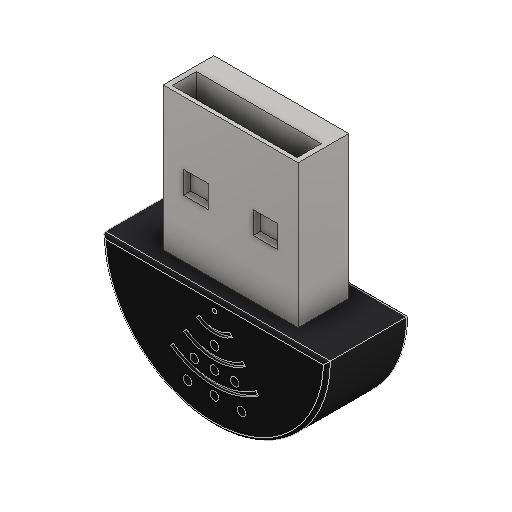
# Autodesk Inventor part: MI-305
Saved by Autodesk Inventor 2027 (Build 310192060, 192F)
## iProperties
Created: 2026-11-22
Part Number: MI-305
Material: 一般
Document SubType Name: Modeling
Designer: 王翊丞
Density: 1 g/cm^3
Appearance: 預設
Title: MI-305 USB 迷你麥克風
Author: 王翊丞
Comments: 照片重建的簡化外形。22 × 19 × 7 mm 為待量測參考尺寸。
Autodesk Inventor part; units mm, degrees
sketch "外殼半橢圓輪廓" plane through (0, 0, 0) normal (0, 0, 1) x (1, 0, 0)
  ellipse E0 centre (0, 0) end of major axis (10, 0) minor radius 9.9 (-10, 0) -> (10, 0) ccw
  line L0 (-10, 0) -> (10, 0)
  dimension "d0" = 10
  dimension "d1" = 9.9
  constraints: 2 end point, 2 horizontal alignment, 1 coincident, 5 other
extrude "外殼擠出" add sketch "外殼半橢圓輪廓" along normal blind 7.4
fillet "外殼上下緣圓角" radius 0.3 4 edges at (0, 0, 0) (0, 0, 7.4) (0, -9.9, 0) (0, -9.9, 7.4)
ref_plane "USB 底面基準" through (0, 0, 1.45) normal (0, 0, 1) x (1, 0, 0)
sketch "USB-A 外廓" plane through (0, 0, 1.45) normal (0, 0, 1) x (1, 0, 0)
  line L0 (-6, 0) -> (6, 0)
  line L1 (6, 0) -> (6, 12.7)
  line L2 (6, 12.7) -> (-6, 12.7)
  line L3 (-6, 12.7) -> (-6, 0)
  point P0 (0, 0)
  dimension "d6" = 6
  dimension "d7" = 12
  dimension "d8" = 12.7
  constraints: 8 end point, 2 parallel, 1 horizontal, 1 horizontal alignment, 1 perpendicular, 1 other
  measures "d6" distance of point (0, 0) L0.start
  measures "d7" distance of L0.start L0.end
  measures "d8" distance of L0.end L1.end
extrude "USB-A 公接頭擠出" add sketch "USB-A 外廓" along normal blind 4.5 separate body
ref_plane "USB 插入端面基準" through (0, 12.7, 0) normal (0, 1, 0) x (-1, 0, 0)
sketch "USB 插入端簡化開口" plane through (0, 12.7, 0) normal (0, 1, 0) x (-1, 0, 0)
  line L0 (-5.55, 3.45) -> (5.55, 3.45)
  line L1 (5.55, 3.45) -> (5.55, 5.6)
  line L2 (5.55, 5.6) -> (-5.55, 5.6)
  line L3 (-5.55, 5.6) -> (-5.55, 3.45)
  point P0 (0, 0)
  dimension "d12" = 5.55
  dimension "d13" = 3.45
  dimension "d14" = 11.1
  dimension "d15" = 2.15
  constraints: 8 end point, 2 parallel, 1 horizontal, 1 perpendicular, 1 other
  measures "d12" horizontal distance of point (0, 0) L0.start
  measures "d13" vertical distance of point (0, 0) L0.start
  measures "d14" distance of L0.start L0.end
  measures "d15" distance of L0.end L1.end
extrude "USB 插入端凹槽" cut sketch "USB 插入端簡化開口" against normal blind 3.1 bodies 2
ref_plane "USB 上表面基準" through (0, 0, 5.95) normal (0, 0, 1) x (1, 0, 0)
sketch "USB 卡扣孔輪廓" plane through (0, 0, 5.95) normal (0, 0, 1) x (1, 0, 0)
  line L0 (-4.2, 5.1) -> (-2, 5.1)
  line L1 (-2, 5.1) -> (-2, 7.1)
  line L2 (-2, 7.1) -> (-4.2, 7.1)
  line L3 (-4.2, 7.1) -> (-4.2, 5.1)
  line L4 (2, 5.1) -> (4.2, 5.1)
  line L5 (4.2, 5.1) -> (4.2, 7.1)
  line L6 (4.2, 7.1) -> (2, 7.1)
  line L7 (2, 7.1) -> (2, 5.1)
  point P0 (0, 0)
  dimension "d19" = 4.2
  dimension "d20" = 5.1
  dimension "d21" = 2.2
  dimension "d22" = 2
  dimension "d23" = 2
  dimension "d24" = 5.1
  dimension "d25" = 2.2
  dimension "d26" = 2
  constraints: 16 end point, 4 parallel, 2 horizontal, 2 perpendicular, 1 other
  measures "d19" horizontal distance of point (0, 0) L0.start
  measures "d20" vertical distance of point (0, 0) L0.start
  measures "d21" distance of L0.start L0.end
  measures "d22" distance of L0.end L1.end
  measures "d23" horizontal distance of point (0, 0) L4.start
  measures "d24" vertical distance of point (0, 0) L4.start
  measures "d25" distance of L4.start L4.end
  measures "d26" distance of L4.end L5.end
extrude "USB 卡扣孔簡化凹槽" cut sketch "USB 卡扣孔輪廓" against normal blind 0.65 bodies 2
ref_plane "收音面基準" through (0, 0, 7.4) normal (0, 0, 1) x (1, 0, 0)
sketch "收音面圓孔配置" plane through (0, 0, 7.4) normal (0, 0, 1) x (1, 0, 0)
  circle A0 centre (0, -0.99) radius 0.195
  circle A1 centre (0, -3.663) radius 0.375
  circle A2 centre (-1.8, -5.544) radius 0.375
  circle A3 centre (0, -5.544) radius 0.375
  circle A4 centre (1.8, -5.544) radius 0.375
  circle A5 centre (-2.4, -7.524) radius 0.375
  circle A6 centre (0, -7.524) radius 0.375
  circle A7 centre (2.4, -7.524) radius 0.375
  point P0 (0, 0)
  dimension "d30" = 0.99
  dimension "d31" = 0.39
  dimension "d32" = 3.663
  dimension "d33" = 0.75
  dimension "d34" = 1.8
  dimension "d35" = 5.544
  dimension "d36" = 0.75
  dimension "d37" = 5.544
  dimension "d38" = 0.75
  dimension "d39" = 1.8
  dimension "d40" = 5.544
  dimension "d41" = 0.75
  dimension "d42" = 2.4
  dimension "d43" = 7.524
  dimension "d44" = 0.75
  dimension "d45" = 7.524
  dimension "d46" = 0.75
  dimension "d47" = 2.4
  dimension "d48" = 7.524
  dimension "d49" = 0.75
  constraints: 8 centre point, 4 vertical alignment, 1 other
  measures "d30" distance of point (0, 0) A0.centre
  measures "d31" diameter of A0
  measures "d32" distance of point (0, 0) A1.centre
  measures "d33" diameter of A1
  measures "d34" horizontal distance of point (0, 0) A2.centre
  measures "d35" vertical distance of point (0, 0) A2.centre
  measures "d36" diameter of A2
  measures "d37" distance of point (0, 0) A3.centre
  measures "d38" diameter of A3
  measures "d39" horizontal distance of point (0, 0) A4.centre
  measures "d40" vertical distance of point (0, 0) A4.centre
  measures "d41" diameter of A4
  measures "d42" horizontal distance of point (0, 0) A5.centre
  measures "d43" vertical distance of point (0, 0) A5.centre
  measures "d44" diameter of A5
  measures "d45" distance of point (0, 0) A6.centre
  measures "d46" diameter of A6
  measures "d47" horizontal distance of point (0, 0) A7.centre
  measures "d48" vertical distance of point (0, 0) A7.centre
  measures "d49" diameter of A7
extrude "收音面盲孔" cut sketch "收音面圓孔配置" against normal blind 0.65 bodies 1
sketch "三道收音面弧槽" plane through (0, 0, 7.4) normal (0, 0, 1) x (1, 0, 0)
  arc A0 (-1.376, -1.9651) -> (1.376, -1.9651) centre (0, 0) ccw
  arc A1 (-1.5768, -2.2518) -> (1.5768, -2.2518) centre (0, 0) ccw
  line L0 (-1.376, -1.9651) -> (-1.5768, -2.2518)
  line L1 (1.376, -1.9651) -> (1.5768, -2.2518)
  arc A2 (-2.5401, -3.6276) -> (2.5401, -3.6276) centre (0, 0) ccw
  arc A3 (-2.7408, -3.9143) -> (2.7408, -3.9143) centre (0, 0) ccw
  line L2 (-2.5401, -3.6276) -> (-2.7408, -3.9143)
  line L3 (2.5401, -3.6276) -> (2.7408, -3.9143)
  arc A4 (-3.7042, -5.2901) -> (3.7042, -5.2901) centre (0, 0) ccw
  arc A5 (-3.9049, -5.5768) -> (3.9049, -5.5768) centre (0, 0) ccw
  line L4 (-3.7042, -5.2901) -> (-3.9049, -5.5768)
  line L5 (3.7042, -5.2901) -> (3.9049, -5.5768)
  dimension "d52" = 2.399
  dimension "d53" = 1.376
  dimension "d54" = 1.376
  dimension "d55" = 2.749
  dimension "d56" = 1.5768
  dimension "d57" = 1.5768
  dimension "d58" = 4.4285
  dimension "d59" = 2.5401
  dimension "d60" = 2.5401
  dimension "d61" = 4.7785
  dimension "d62" = 2.7408
  dimension "d63" = 2.7408
  dimension "d64" = 6.458
  dimension "d65" = 3.7042
  dimension "d66" = 3.7042
  dimension "d67" = 6.808
  dimension "d68" = 3.9049
  dimension "d69" = 3.9049
  constraints: 12 end point, 12 point on circle, 6 centre point, 6 coincident, 1 other
  measures "d52" radius of A0
  measures "d53" horizontal distance of point (0, 0) L0.start
  measures "d54" horizontal distance of point (0, 0) L1.start
  measures "d55" radius of A1
  measures "d56" horizontal distance of point (0, 0) L0.end
  measures "d57" horizontal distance of point (0, 0) L1.end
  measures "d58" radius of A2
  measures "d59" horizontal distance of point (0, 0) L2.start
  measures "d60" horizontal distance of point (0, 0) L3.start
  measures "d61" radius of A3
  measures "d62" horizontal distance of point (0, 0) L2.end
  measures "d63" horizontal distance of point (0, 0) L3.end
  measures "d64" radius of A4
  measures "d65" horizontal distance of point (0, 0) L4.start
  measures "d66" horizontal distance of point (0, 0) L5.start
  measures "d67" radius of A5
  measures "d68" horizontal distance of point (0, 0) L4.end
  measures "d69" horizontal distance of point (0, 0) L5.end
extrude "收音面弧槽切除" cut sketch "三道收音面弧槽" against normal blind 0.25 bodies 1
equation "\"d0\" = 0.5 * HousingWidth"
equation "\"d1\" = HousingDepth"
equation "\"d2\" = HousingThickness"
equation "\"d4\" = HousingEdgeRadius"
equation "\"d6\" = 0.5 * USBWidth - USBOffsetX"
equation "\"d7\" = USBWidth"
equation "\"d8\" = USBExposed"
equation "\"d9\" = USBThickness"
equation "\"d19\" = 0.35 * USBWidth - USBOffsetX"
equation "\"d23\" = 0.166667 * USBWidth + USBOffsetX"
equation "\"d30\" = 0.1 * HousingDepth"
equation "\"d31\" = 0.52 * PortDiameter"
equation "\"d32\" = 0.37 * HousingDepth"
equation "\"d33\" = PortDiameter"
equation "\"d34\" = 0.09 * HousingWidth"
equation "\"d35\" = 0.56 * HousingDepth"
equation "\"d36\" = PortDiameter"
equation "\"d37\" = 0.56 * HousingDepth"
equation "\"d38\" = PortDiameter"
equation "\"d39\" = 0.09 * HousingWidth"
equation "\"d40\" = 0.56 * HousingDepth"
equation "\"d41\" = PortDiameter"
equation "\"d42\" = 0.12 * HousingWidth"
equation "\"d43\" = 0.76 * HousingDepth"
equation "\"d44\" = PortDiameter"
equation "\"d45\" = 0.76 * HousingDepth"
equation "\"d46\" = PortDiameter"
equation "\"d47\" = 0.12 * HousingWidth"
equation "\"d48\" = 0.76 * HousingDepth"
equation "\"d49\" = PortDiameter"
equation "\"d50\" = PortDepth"
equation "\"d52\" = 0.26 * HousingDepth - 0.5 * GrooveWidth"
equation "\"d53\" = -0.286788 * GrooveWidth + 0.14913 * HousingDepth"
equation "\"d54\" = -0.286788 * GrooveWidth + 0.14913 * HousingDepth"
equation "\"d55\" = 0.26 * HousingDepth + 0.5 * GrooveWidth"
equation "\"d56\" = 0.286788 * GrooveWidth + 0.14913 * HousingDepth"
equation "\"d57\" = 0.286788 * GrooveWidth + 0.14913 * HousingDepth"
equation "\"d58\" = 0.465 * HousingDepth - 0.5 * GrooveWidth"
equation "\"d59\" = -0.286788 * GrooveWidth + 0.266713 * HousingDepth"
equation "\"d60\" = -0.286788 * GrooveWidth + 0.266713 * HousingDepth"
equation "\"d61\" = 0.465 * HousingDepth + 0.5 * GrooveWidth"
equation "\"d62\" = 0.286788 * GrooveWidth + 0.266713 * HousingDepth"
equation "\"d63\" = 0.286788 * GrooveWidth + 0.266713 * HousingDepth"
equation "\"d64\" = 0.67 * HousingDepth - 0.5 * GrooveWidth"
equation "\"d65\" = -0.286788 * GrooveWidth + 0.384296 * HousingDepth"
equation "\"d66\" = -0.286788 * GrooveWidth + 0.384296 * HousingDepth"
equation "\"d67\" = 0.67 * HousingDepth + 0.5 * GrooveWidth"
equation "\"d68\" = 0.286788 * GrooveWidth + 0.384296 * HousingDepth"
equation "\"d69\" = 0.286788 * GrooveWidth + 0.384296 * HousingDepth"
equation "\"d70\" = GrooveDepth"
equation "\"HousingDepth\" = 9.9"
equation "\"HousingThickness\" = 7.4"
equation "\"HousingEdgeRadius\" = 0.3"
equation "\"USBWidth\" = 12"
equation "\"USBThickness\" = 4.5"
equation "\"USBExposed\" = 12.7"
equation "\"USBOffsetX\" = 0"
equation "\"USBOffsetZ\" = 0"
equation "\"PortDiameter\" = 0.75"
equation "\"PortDepth\" = 0.65"
equation "\"GrooveWidth\" = 0.35"
equation "\"GrooveDepth\" = 0.25"
equation "\"OverallLength\" = HousingDepth + USBExposed"
equation "\"d5\" = 0.5 * HousingThickness - 0.5 * USBThickness + USBOffsetZ"
equation "\"d11\" = USBExposed"
equation "\"d18\" = 0.5 * HousingThickness + 0.5 * USBThickness + USBOffsetZ"
equation "\"d29\" = HousingThickness"
equation "\"HousingWidth\" = 20"
